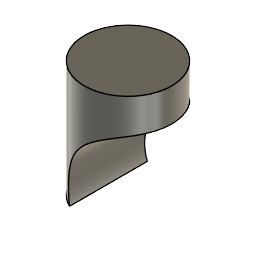
Cushion (Autodesk Fusion 360 design; units mm, degrees)
Autodesk Fusion 360 part; units mm, degrees
sketch "Sketch1" plane through (0, 0, 0) normal (0, 0, 1) x (1, 0, 0)
  circle A0 centre (0, 0) radius 3.5719
  dimension "d1" = 7.1437
  constraint coincident A0.centre origin
  measures "d1" diameter of A0
extrude "Extrude1" add sketch "Sketch1" along normal blind 9.525
sketch "Sketch2" plane through (0, 0, 0) normal (0, 1, 0) x (1, 0, 0)
  circle A0 centre (3.81, -1.27) radius 5.5563
  dimension "d4" = 11.1125
  measures "d4" diameter of A0
extrude "Extrude2" cut sketch "Sketch2" along normal blind 12.7 and the other way blind 12.7
equation "d1 = ( 9 / 32 ) * 1 in"
equation "d2 = ( 3 / 8 ) * 1 in"
equation "d4 = ( 7 / 16 ) * 1 in"
